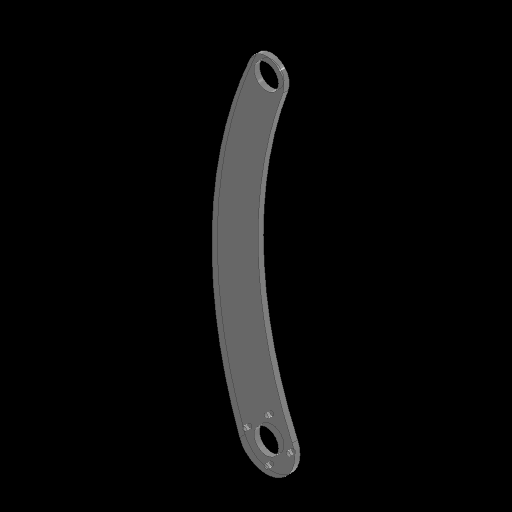
# Autodesk Inventor part: INTK_002_left bar
Saved by Autodesk Inventor 2027.1 (Build 311270010, 270A)
## iProperties
Created: 2026-11-21
Part Number: INTK_002_left bar
Material: Polycarbonate, Clear
Document SubType Name: Modeling
Designer: Stanley Ruangsuwan
Density: 1.2 g/cm^3
Appearance: Polycarbonate - Clear
Author: Stanley Ruangsuwan
Autodesk Inventor part; units mm, degrees
ref_plane "YZ Plane" through (0, 0, 0) normal (1, 0, 0) x (0, 1, 0)
ref_plane "XZ Plane" through (0, 0, 0) normal (0, 1, 0) x (-1, 0, 0)
ref_plane "XY Plane" through (0, 0, 0) normal (0, 0, 1) x (1, 0, 0)
sketch "Sketch1" plane through (0, 0, 0) normal (0, 0, 1) x (1, 0, 0)
  circle A0 centre (0, 0) radius 33.02
  circle A1 centre (0, 367.5038) radius 14.2875
  circle A2 centre (0, 0) radius 14.2875
  circle A3 centre (0, 25.4) radius 2.4765
  circle A4 centre (-25.4, 0) radius 2.4765
  circle A5 centre (0, -25.4) radius 2.4765
  circle A6 centre (25.4, 0) radius 2.4765
  circle A7 centre (0, 367.5038) radius 20.6375
  arc A8 (19.3333, 360.2838) -> (30.1531, 13.4577) centre (448.3066, 200.0845) ccw
  arc A9 (-18.8457, 375.9149) -> (-30.9333, -11.552) centre (448.3066, 167.4193) ccw
  circle A10 centre (0, 25.4) radius 2.4765
  dimension "d1" = 66.04
  dimension "d2" = 28.575
  dimension "d5" = 28.575
  dimension "d6" = 4.953
  dimension "d7" = 25.4
  dimension "d10" = 360
  dimension "d12" = 6.35
  dimension "d15" = 457.9104
  dimension "d16" = 367.5038
  constraints: 11 centre point, 8 point on circle, 4 tangent, 3 coincident, 2 vertical alignment, 1 concentric, 1 horizontal alignment, 9 other
  measures "d1" diameter of A0
  measures "d2" diameter of A1
  measures "d5" diameter of A2
  measures "d6" diameter of A3
  measures "d7" distance of A2.centre A3.centre
  measures "d12" radial gap between concentric circles of A1 A7
  measures "d15" radius of A8
  measures "d16" distance of A0.centre A1.centre
extrude "Extrusion1" add sketch "Sketch1" along normal blind 6.35
body "Solid1"
